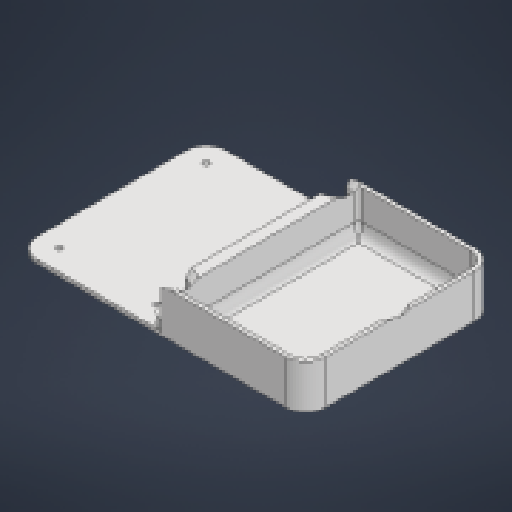
# Autodesk Inventor part: plaque1intboite
Saved by Autodesk Inventor 2026.1 (Build 301233020, 233B)
## iProperties
Created: 2026-05-26
Part Number: plaque1intboite
Material: Générique
Document SubType Name: Modeling
Designer: matpo
Density: 1 g/cm^3
Appearance: Par défaut
Author: matpo
Autodesk Inventor part; units mm, degrees
ref_plane "YZ Plane" through (0, 0, 0) normal (1, 0, 0) x (0, 1, 0)
ref_plane "XZ Plane" through (0, 0, 0) normal (0, 1, 0) x (-1, 0, 0)
ref_plane "XY Plane" through (0, 0, 0) normal (0, 0, 1) x (1, 0, 0)
sketch "Esquisse1" plane through (0, 0, 0) normal (0, 1, 0) x (-1, 0, 0)
  line L0 (-62.5, -47.5) -> (62.5, -47.5)
  line L1 (72.5, -37.5) -> (72.5, 37.5)
  line L2 (62.5, 47.5) -> (-62.5, 47.5)
  line L3 (-72.5, 37.5) -> (-72.5, -37.5)
  line L4 (-72.5, -47.5) -> (72.5, 47.5) construction
  line L5 (72.5, -47.5) -> (-72.5, 47.5) construction
  arc A0 (72.5, 37.5) -> (62.5, 47.5) centre (62.5, 37.5) ccw
  arc A1 (62.5, -47.5) -> (72.5, -37.5) centre (62.5, -37.5) ccw
  arc A2 (-72.5, -37.5) -> (-62.5, -47.5) centre (-62.5, -37.5) ccw
  arc A3 (-62.5, 47.5) -> (-72.5, 37.5) centre (-62.5, 37.5) ccw
  line L6 (62.5, 45.5) -> (-62.5, 45.5) construction
  arc A4 (-62.5, 45.5) -> (-70.5, 37.5) centre (-62.5, 37.5) ccw construction
  line L7 (-70.5, 37.5) -> (-70.5, -37.5) construction
  arc A5 (-70.5, -37.5) -> (-62.5, -45.5) centre (-62.5, -37.5) ccw construction
  line L8 (-62.5, -45.5) -> (62.5, -45.5) construction
  arc A6 (62.5, -45.5) -> (70.5, -37.5) centre (62.5, -37.5) ccw construction
  line L9 (70.5, -37.5) -> (70.5, 37.5) construction
  arc A7 (70.5, 37.5) -> (62.5, 45.5) centre (62.5, 37.5) ccw construction
  line L10 (8, 42) -> (67, 42) construction
  line L11 (67, 42) -> (67, -42) construction
  line L12 (67, -42) -> (8, -42) construction
  line L13 (8, -42) -> (8, 42) construction
  line L14 (8, 42) -> (67, -42) construction
  line L15 (67, 42) -> (8, -42) construction
  circle A8 centre (62, 37) radius 1.6
  line L16 (37.5, 0) -> (37.5, 42) construction
  line L17 (37.5, 0) -> (67, 0) construction
  circle A9 centre (13, 37) radius 1.6
  circle A10 centre (62, -37) radius 1.6
  circle A11 centre (13, -37) radius 1.6
  point P0 (0, 0)
  dimension "d0" = 145
  dimension "d1" = 95
  dimension "d2" = 10
  dimension "d3" = 2
  dimension "d30" = 5.5
  dimension "d31" = 5.5
  dimension "d32" = 59
  dimension "d33" = 84
  dimension "d34" = 3.2
  dimension "d35" = 5
  dimension "d36" = 5
  constraints: 36 end point, 16 point on circle, 12 centre point, 8 point on line, 8 tangent, 6 midpoint, 6 parallel, 3 equal radius, 3 perpendicular, 3 symmetric about line, 2 horizontal, 1 horizontal alignment, 10 other
  measures "d0" distance of L5.end L4.end
  measures "d1" distance of L5.start L4.end
  measures "d2" radius of A0
  measures "d3" radial gap between concentric circles of A0 A7
  measures "d30" distance between parallel lines of L1 L11
  measures "d31" distance between parallel lines of L0 L12
  measures "d32" distance between parallel lines of L13 L11
  measures "d33" distance between parallel lines of L10 L12
  measures "d34" diameter of A8
  measures "d35" distance from line of L10 A8.centre
  measures "d36" distance from line of L11 A8.centre
extrude "Extrusion1" add sketch "Esquisse1" along normal blind 2
sketch "Esquisse2" plane through (0, 2, 0) normal (0, 1, 0) x (1, 0, 0)
  arc A0 (-62.5, 47.5) -> (-72.5, 37.5) centre (-62.5, 37.5) ccw projected
  line L0 (-72.5, 37.5) -> (-72.5, -37.5) projected
  arc A1 (-72.5, -37.5) -> (-62.5, -47.5) centre (-62.5, -37.5) ccw projected
  line L1 (-62.5, -47.5) -> (62.5, -47.5) projected
  arc A2 (62.5, -47.5) -> (72.5, -37.5) centre (62.5, -37.5) ccw projected
  line L2 (72.5, -37.5) -> (72.5, 37.5) projected
  arc A3 (72.5, 37.5) -> (62.5, 47.5) centre (62.5, 37.5) ccw projected
  line L3 (62.5, 47.5) -> (-62.5, 47.5) projected
  line L4 (0, 47.5) -> (0, -47.5)
  line L5 (8, -45.5) -> (62.5, -45.5)
  arc A4 (62.5, -45.5) -> (70.5, -37.5) centre (62.5, -37.5) ccw
  line L6 (70.5, -37.5) -> (70.5, 37.5)
  arc A5 (70.5, 37.5) -> (62.5, 45.5) centre (62.5, 37.5) ccw
  line L7 (62.5, 45.5) -> (8, 45.5)
  line L8 (6, 43.5) -> (6, -43.5)
  arc A6 (6, -43.5) -> (8, -45.5) centre (8, -43.5) ccw
  arc A7 (8, 45.5) -> (6, 43.5) centre (8, 43.5) ccw
  circle A8 centre (65.5, 0) radius 5
  circle A9 centre (-65.5, 0) radius 5
  circle A10 centre (0, 40.5) radius 5
  line L9 (8, 45.5) -> (0, 45.5) construction
  line L10 (65.5, 0) -> (-65.5, 0) construction
  circle A11 centre (0, -40.5) radius 5
  point P0 (0, 0)
  point P1 (6, 0)
  point P2 (70.5, 0)
  point P3 (0, 0)
  point P4 (0, 35.5)
  point P5 (0, -35.5)
  point P6 (0, -45.5)
  dimension "d9" = 10
  dimension "d6" = 2
  dimension "d7" = 6
  dimension "d8" = 2
  constraints: 14 end point, 8 point on circle, 6 centre point, 5 midpoint, 5 tangent, 2 horizontal alignment, 2 point on line, 2 symmetric about line, 1 equal radius, 1 horizontal, 1 parallel, 1 perpendicular, 1 vertical alignment, 11 other
  measures "d6" distance between parallel lines of L3 L7
  measures "d7" distance between parallel lines of L4 L8
  measures "d8" radius of A6
extrude "Extrusion2" add sketch "Esquisse2" along normal blind 20 contours L3 A3 L2 A2 L1 L4 A11 A10
sketch "Esquisse3" plane through (0, 2, 0) normal (0, 1, 0) x (1, 0, 0)
  arc A0 (0, 35.5) -> (0, 45.5) centre (0, 40.5) ccw projected
  arc A1 (0, -45.5) -> (0, -35.5) centre (0, -40.5) ccw projected
  circle A2 centre (-65.5, 0) radius 5 projected
  circle A3 centre (-65.5, 0) radius 7
  line L0 (-72.5, 37.5) -> (-72.5, -37.5) projected
  line L1 (72.5, -37.5) -> (72.5, 37.5) projected
  circle A4 centre (0, -40.5) radius 5 projected
  circle A5 centre (0, 40.5) radius 5 projected
  circle A6 centre (0, 40.5) radius 7
  circle A7 centre (0, -40.5) radius 7
  point P0 (0, 0)
  point P1 (-72.5, 0)
  point P2 (72.5, 0)
  point P3 (0, 47.5)
  point P4 (0, -47.5)
  constraints: 2 midpoint, 2 vertical alignment, 1 horizontal alignment, 6 other
extrude "Extrusion3" add sketch "Esquisse3" along normal blind 5 contours A6 | A7
sketch "Esquisse4" plane through (0, 2, 0) normal (0, 1, 0) x (1, 0, 0)
  line L0 (6, -43.5) -> (6, 43.5) projected
  arc A0 (6, -43.5) -> (8, -45.5) centre (8, -43.5) ccw projected
  line L1 (62.5, -45.5) -> (8, -45.5) projected
  arc A1 (62.5, -45.5) -> (70.5, -37.5) centre (62.5, -37.5) ccw projected
  line L2 (70.5, 37.5) -> (70.5, -37.5) projected
  arc A2 (8, 45.5) -> (6, 43.5) centre (8, 43.5) ccw projected
  line L3 (8, 45.5) -> (62.5, 45.5) projected
  line L4 (20.9673, 45.5) -> (20.1685, -45.5)
  point P0 (0, 0)
  constraints: 2 end point, 2 point on line
extrude "Extrusion4" cut sketch "Esquisse4" along normal up to surface (20 mm away)
fillet "Congé1" radius 5 9 edges at (6.5858, 2, -44.9142) (6, 2, 0) (6.5858, 2, 44.9142) (35.25, 2, 45.5) (68.1569, 2, 43.1569) (70.5, 2, 0) (68.1569, 2, -43.1569) (35.25, 2, -45.5) (0, 2, 0)
sketch "Esquisse5" plane through (0, 0, 0) normal (0, -1, 0) x (1, 0, 0)
  circle A0 centre (0, -40.5) radius 5 projected
  circle A1 centre (65.5, 0) radius 5 projected
  circle A2 centre (0, 40.5) radius 5 projected
  circle A3 centre (-13, -37) radius 1.6 projected
  circle A4 centre (-62, -37) radius 1.6 projected
  circle A5 centre (-13, 37) radius 1.6 projected
  circle A6 centre (-62, 37) radius 1.6 projected
  point P0 (0, 0)
hole "Perçage1" at (0, 0, 40.5) at (0, 0, -40.5) at (-13, 0, -37) at (-13, 0, 37) at (-62, 0, 37) at (-62, 0, -37) direction (0, 1, 0) diameter 3.2 depth 8 counterbore diameter 6.2 counterbore depth 1
chamfer "Chanfrein1" distance 3 angle 45 2 edges at (5, 22, 40.5) (5, 22, -40.5)
sketch "Esquisse7" plane through (-62.5, 0, 47.5) normal (0, 0, 1) x (1, 0, 0)
  line L0 (62.5, 7) -> (62.5, 21) projected
  line L1 (62.5, 2) -> (62.5, 7) projected
  line L2 (0, 2) -> (62.5, 2) projected
  line L3 (0, 0) -> (0, 2) projected
  line L4 (0, 0) -> (125, 0) projected
  line L5 (125, 0) -> (125, 22) projected
  line L6 (66.373, 22) -> (125, 22) projected
  line L7 (81.3302, 14.2139) -> (73.6698, 7.7861) construction
  line L8 (79.7233, 16.129) -> (72.0628, 9.7012)
  line L9 (75.2767, 5.871) -> (82.9372, 12.2988)
  arc A0 (82.9372, 12.2988) -> (79.7233, 16.129) centre (81.3302, 14.2139) ccw
  arc A1 (72.0628, 9.7012) -> (75.2767, 5.871) centre (73.6698, 7.7861) ccw
  line L10 (125, 22) -> (133, 22) construction
  line L11 (125, 22) -> (62.5, 22) construction
  line L12 (62.5, 22) -> (62.5, 0) construction
  line L13 (62.5, 0) -> (125, 0) construction
  line L14 (125, 0) -> (125, 22) construction
  line L15 (62.5, 11) -> (125, 11) construction
  line L16 (85.2767, 5.871) -> (92.9372, 12.2988)
  arc A2 (82.0628, 9.7012) -> (85.2767, 5.871) centre (83.6698, 7.7861) ccw
  line L17 (89.7233, 16.129) -> (82.0628, 9.7012)
  arc A3 (92.9372, 12.2988) -> (89.7233, 16.129) centre (91.3302, 14.2139) ccw
  line L18 (95.2767, 5.871) -> (102.9372, 12.2988)
  arc A4 (92.0628, 9.7012) -> (95.2767, 5.871) centre (93.6698, 7.7861) ccw
  line L19 (99.7233, 16.129) -> (92.0628, 9.7012)
  arc A5 (102.9372, 12.2988) -> (99.7233, 16.129) centre (101.3302, 14.2139) ccw
  line L20 (105.2767, 5.871) -> (112.9372, 12.2988)
  arc A6 (102.0628, 9.7012) -> (105.2767, 5.871) centre (103.6698, 7.7861) ccw
  line L21 (109.7233, 16.129) -> (102.0628, 9.7012)
  arc A7 (112.9372, 12.2988) -> (109.7233, 16.129) centre (111.3302, 14.2139) ccw
  point P0 (77.5, 11)
  dimension "d37" = 5
  dimension "d38" = 10
  dimension "d39" = 40
  dimension "d40" = 15
  dimension "d43" = 10
  constraints: 30 end point, 16 point on circle, 8 centre point, 4 tangent, 3 midpoint, 3 parallel, 2 horizontal, 1 perpendicular, 1 point on line, 31 other
  measures "d37" distance between parallel lines of L8 L9
  measures "d38" distance of L7.start L7.end
  measures "d39" angle of L4 L7
  measures "d40" distance from line of L0 point (77.5, 11)
  measures "d43" distance of L9.start L16.start
extrude "Extrusion5" cut sketch "Esquisse7" against normal through all
sketch "Esquisse8" plane through (72.5, 0, 37.5) normal (1, 0, 0) x (0, 0, -1)
  line L0 (0, 22) -> (75, 22) projected
  line L1 (0, 0) -> (0, 22) projected
  line L2 (0, 0) -> (75, 0) projected
  line L3 (75, 0) -> (75, 22) projected
  line L4 (75, 0.1027) -> (75, 22)
  line L5 (10, 16) -> (10, 6) construction
  line L6 (7.5, 16) -> (7.5, 6)
  line L7 (12.5, 6) -> (12.5, 16)
  arc A0 (12.5, 16) -> (7.5, 16) centre (10, 16) ccw
  arc A1 (7.5, 6) -> (12.5, 6) centre (10, 6) ccw
  line L8 (75, 22) -> (0, 22) construction
  line L9 (0, 22) -> (0, 0) construction
  line L10 (0, 0) -> (75, 0) construction
  line L11 (75, 0) -> (75, 22) construction
  line L12 (0, 11) -> (75, 11) construction
  arc A2 (25.5, 6) -> (30.5, 6) centre (28, 6) ccw
  line L13 (30.5, 6) -> (30.5, 16)
  line L14 (25.5, 16) -> (25.5, 6)
  arc A3 (30.5, 16) -> (25.5, 16) centre (28, 16) ccw
  arc A4 (43.5, 6) -> (48.5, 6) centre (46, 6) ccw
  line L15 (48.5, 6) -> (48.5, 16)
  line L16 (43.5, 16) -> (43.5, 6)
  arc A5 (48.5, 16) -> (43.5, 16) centre (46, 16) ccw
  arc A6 (61.5, 6) -> (66.5, 6) centre (64, 6) ccw
  line L17 (66.5, 6) -> (66.5, 16)
  line L18 (61.5, 16) -> (61.5, 6)
  arc A7 (66.5, 16) -> (61.5, 16) centre (64, 16) ccw
  point P0 (37.5, 0)
  point P1 (10, 11)
  dimension "d54" = 5
  dimension "d55" = 10
  dimension "d59" = 10
  dimension "d62" = 18
  constraints: 32 end point, 16 point on circle, 8 centre point, 4 tangent, 3 midpoint, 3 parallel, 2 horizontal, 1 perpendicular, 1 point on line, 1 vertical, 30 other
  measures "d54" distance between parallel lines of L6 L7
  measures "d55" distance of L5.start L5.end
  measures "d59" distance from line of L1 point (10, 11)
  measures "d62" distance of L5.end A2.centre
extrude "Extrusion6" cut sketch "Esquisse8" against normal blind 8 contours A0 L7 A1 L6 | L14 A3 L13 A2 | L16 A5 L15 A4 | L18 A7 L17 A6
equation "\"d31\" = d30"
